Autodesk Fusion 360 part; units mm, degrees
(part 3 of 8)
sketch "SW2 receiver profile" plane through (0, -2.1431, 24.4961) normal (0, -0.087156, 0.996195) x (1, 0, 0)
  line L0 (30.8, 17.6972) -> (49.2, 17.6972)
  line L1 (49.2, 17.6972) -> (49.2, 35.2972)
  line L2 (49.2, 35.2972) -> (30.8, 35.2972)
  line L3 (30.8, 35.2972) -> (30.8, 17.6972)
  dimension "d1000" = 30.8
  dimension "d1001" = 17.6972
  dimension "d1002" = 18.4
  dimension "d1003" = 17.6
  constraint horizontal L0
  constraint vertical L1
  constraint horizontal L2
  constraint vertical L3
  measures "d1000" horizontal distance of origin L0.start
  measures "d1001" vertical distance of origin L0.start
  measures "d1002" distance of L0.start L0.end
  measures "d1003" distance of L0.end L1.end
extrude "SW2 integrated receiver" add sketch "SW2 receiver profile" against normal blind 11.5 bodies 2
sketch "SW2 switch lower clearance profile" plane through (0, -2.1431, 24.4961) normal (0, -0.087156, 0.996195) x (1, 0, 0)
  line L0 (32, 18.4972) -> (48, 18.4972)
  line L1 (48, 18.4972) -> (48, 34.4972)
  line L2 (48, 34.4972) -> (32, 34.4972)
  line L3 (32, 34.4972) -> (32, 18.4972)
  dimension "d1006" = 32
  dimension "d1007" = 18.4972
  dimension "d1008" = 16
  dimension "d1009" = 16
  constraint horizontal L0
  constraint vertical L1
  constraint horizontal L2
  constraint vertical L3
  measures "d1006" horizontal distance of origin L0.start
  measures "d1007" vertical distance of origin L0.start
  measures "d1008" distance of L0.start L0.end
  measures "d1009" distance of L0.end L1.end
extrude "SW2 switch lower clearance" cut sketch "SW2 switch lower clearance profile" against normal blind 5.5 bodies 2
sketch "SW2 holder pocket profile" plane through (0, -1.6638, 19.017) normal (0, -0.087156, 0.996195) x (1, 0, 0)
  line L0 (34.2843, 21.4226) -> (45.7157, 21.4226)
  line L1 (45.7157, 21.4226) -> (45.7157, 31.5717)
  line L2 (45.7157, 31.5717) -> (34.2843, 31.5717)
  line L3 (34.2843, 31.5717) -> (34.2843, 21.4226)
  dimension "d1012" = 34.2843
  dimension "d1013" = 21.4226
  dimension "d1014" = 11.4315
  dimension "d1015" = 10.1491
  constraint horizontal L0
  constraint vertical L1
  constraint horizontal L2
  constraint vertical L3
  measures "d1012" horizontal distance of origin L0.start
  measures "d1013" vertical distance of origin L0.start
  measures "d1014" distance of L0.start L0.end
  measures "d1015" distance of L0.end L1.end
extrude "SW2 open-bottom holder pocket" cut sketch "SW2 holder pocket profile" against normal blind 6.2 bodies 2
sketch "SW2 spring 1 release 1 profile" plane through (0, -2.056, 23.4999) normal (0, -0.087156, 0.996195) x (1, 0, 0)
  line L0 (30.7, 28.5972) -> (34.2843, 28.5972)
  line L1 (34.2843, 28.5972) -> (34.2843, 29.1972)
  line L2 (34.2843, 29.1972) -> (30.7, 29.1972)
  line L3 (30.7, 29.1972) -> (30.7, 28.5972)
  dimension "d1018" = 30.7
  dimension "d1019" = 28.5972
  dimension "d1020" = 3.5843
  dimension "d1021" = 0.6
  constraint horizontal L0
  constraint vertical L1
  constraint horizontal L2
  constraint vertical L3
  measures "d1018" horizontal distance of origin L0.start
  measures "d1019" vertical distance of origin L0.start
  measures "d1020" distance of L0.start L0.end
  measures "d1021" distance of L0.end L1.end
extrude "SW2 spring 1 release 1" cut sketch "SW2 spring 1 release 1 profile" against normal blind 10.7 bodies 2
sketch "SW2 spring 1 release 2 profile" plane through (0, -2.056, 23.4999) normal (0, -0.087156, 0.996195) x (1, 0, 0)
  line L0 (30.7, 31.1972) -> (34.2843, 31.1972)
  line L1 (34.2843, 31.1972) -> (34.2843, 31.7972)
  line L2 (34.2843, 31.7972) -> (30.7, 31.7972)
  line L3 (30.7, 31.7972) -> (30.7, 31.1972)
  dimension "d1024" = 30.7
  dimension "d1025" = 31.1972
  dimension "d1026" = 3.5843
  dimension "d1027" = 0.6
  constraint horizontal L0
  constraint vertical L1
  constraint horizontal L2
  constraint vertical L3
  measures "d1024" horizontal distance of origin L0.start
  measures "d1025" vertical distance of origin L0.start
  measures "d1026" distance of L0.start L0.end
  measures "d1027" distance of L0.end L1.end
extrude "SW2 spring 1 release 2" cut sketch "SW2 spring 1 release 2 profile" against normal blind 10.7 bodies 2
sketch "SW2 spring 1 inner clearance profile" plane through (0, -1.6638, 19.017) normal (0, -0.087156, 0.996195) x (1, 0, 0)
  line L0 (31.6, 29.1972) -> (34.2843, 29.1972)
  line L1 (34.2843, 29.1972) -> (34.2843, 31.1972)
  line L2 (34.2843, 31.1972) -> (31.6, 31.1972)
  line L3 (31.6, 31.1972) -> (31.6, 29.1972)
  dimension "d1030" = 31.6
  dimension "d1031" = 29.1972
  dimension "d1032" = 2.6843
  dimension "d1033" = 2
  constraint horizontal L0
  constraint vertical L1
  constraint horizontal L2
  constraint vertical L3
  measures "d1030" horizontal distance of origin L0.start
  measures "d1031" vertical distance of origin L0.start
  measures "d1032" distance of L0.start L0.end
  measures "d1033" distance of L0.end L1.end
extrude "SW2 spring 1 inner clearance" cut sketch "SW2 spring 1 inner clearance profile" against normal blind 6.2 bodies 2
sketch "SW2 spring 1 hook profile" plane through (0, -1.2106, 13.8368) normal (0, -0.087156, 0.996195) x (1, 0, 0)
  line L0 (30.8, 29.1972) -> (34.7843, 29.1972)
  line L1 (34.7843, 29.1972) -> (34.7843, 31.1972)
  line L2 (34.7843, 31.1972) -> (30.8, 31.1972)
  line L3 (30.8, 31.1972) -> (30.8, 29.1972)
  dimension "d1036" = 30.8
  dimension "d1037" = 29.1972
  dimension "d1038" = 3.9843
  dimension "d1039" = 2
  constraint horizontal L0
  constraint vertical L1
  constraint horizontal L2
  constraint vertical L3
  measures "d1036" horizontal distance of origin L0.start
  measures "d1037" vertical distance of origin L0.start
  measures "d1038" distance of L0.start L0.end
  measures "d1039" distance of L0.end L1.end
extrude "SW2 spring 1 retaining hook" add sketch "SW2 spring 1 hook profile" against normal blind 0.8 bodies 2
chamfer "SW2 spring 1 45 degree lead-in" distance 0.35 angle 45 1 edges at (34.7843, 28.9414, 15.6717) tangent chain off on bodies 2
sketch "SW2 spring 2 release 1 profile" plane through (0, -2.056, 23.4999) normal (0, -0.087156, 0.996195) x (1, 0, 0)
  line L0 (45.7157, 28.5972) -> (49.3, 28.5972)
  line L1 (49.3, 28.5972) -> (49.3, 29.1972)
  line L2 (49.3, 29.1972) -> (45.7157, 29.1972)
  line L3 (45.7157, 29.1972) -> (45.7157, 28.5972)
  dimension "d1043" = 45.7157
  dimension "d1044" = 28.5972
  dimension "d1045" = 3.5843
  dimension "d1046" = 0.6
  constraint horizontal L0
  constraint vertical L1
  constraint horizontal L2
  constraint vertical L3
  measures "d1043" horizontal distance of origin L0.start
  measures "d1044" vertical distance of origin L0.start
  measures "d1045" distance of L0.start L0.end
  measures "d1046" distance of L0.end L1.end
extrude "SW2 spring 2 release 1" cut sketch "SW2 spring 2 release 1 profile" against normal blind 10.7 bodies 2
sketch "SW2 spring 2 release 2 profile" plane through (0, -2.056, 23.4999) normal (0, -0.087156, 0.996195) x (1, 0, 0)
  line L0 (45.7157, 31.1972) -> (49.3, 31.1972)
  line L1 (49.3, 31.1972) -> (49.3, 31.7972)
  line L2 (49.3, 31.7972) -> (45.7157, 31.7972)
  line L3 (45.7157, 31.7972) -> (45.7157, 31.1972)
  dimension "d1049" = 45.7157
  dimension "d1050" = 31.1972
  dimension "d1051" = 3.5843
  dimension "d1052" = 0.6
  constraint horizontal L0
  constraint vertical L1
  constraint horizontal L2
  constraint vertical L3
  measures "d1049" horizontal distance of origin L0.start
  measures "d1050" vertical distance of origin L0.start
  measures "d1051" distance of L0.start L0.end
  measures "d1052" distance of L0.end L1.end
extrude "SW2 spring 2 release 2" cut sketch "SW2 spring 2 release 2 profile" against normal blind 10.7 bodies 2
sketch "SW2 spring 2 inner clearance profile" plane through (0, -1.6638, 19.017) normal (0, -0.087156, 0.996195) x (1, 0, 0)
  line L0 (45.7157, 29.1972) -> (48.4, 29.1972)
  line L1 (48.4, 29.1972) -> (48.4, 31.1972)
  line L2 (48.4, 31.1972) -> (45.7157, 31.1972)
  line L3 (45.7157, 31.1972) -> (45.7157, 29.1972)
  dimension "d1055" = 45.7157
  dimension "d1056" = 29.1972
  dimension "d1057" = 2.6843
  dimension "d1058" = 2
  constraint horizontal L0
  constraint vertical L1
  constraint horizontal L2
  constraint vertical L3
  measures "d1055" horizontal distance of origin L0.start
  measures "d1056" vertical distance of origin L0.start
  measures "d1057" distance of L0.start L0.end
  measures "d1058" distance of L0.end L1.end
extrude "SW2 spring 2 inner clearance" cut sketch "SW2 spring 2 inner clearance profile" against normal blind 6.2 bodies 2
sketch "SW2 spring 2 hook profile" plane through (0, -1.2106, 13.8368) normal (0, -0.087156, 0.996195) x (1, 0, 0)
  line L0 (45.2157, 29.1972) -> (49.2, 29.1972)
  line L1 (49.2, 29.1972) -> (49.2, 31.1972)
  line L2 (49.2, 31.1972) -> (45.2157, 31.1972)
  line L3 (45.2157, 31.1972) -> (45.2157, 29.1972)
  dimension "d1061" = 45.2157
  dimension "d1062" = 29.1972
  dimension "d1063" = 3.9843
  dimension "d1064" = 2
  constraint horizontal L0
  constraint vertical L1
  constraint horizontal L2
  constraint vertical L3
  measures "d1061" horizontal distance of origin L0.start
  measures "d1062" vertical distance of origin L0.start
  measures "d1063" distance of L0.start L0.end
  measures "d1064" distance of L0.end L1.end
extrude "SW2 spring 2 retaining hook" add sketch "SW2 spring 2 hook profile" against normal blind 0.8 bodies 2
chamfer "SW2 spring 2 45 degree lead-in" distance 0.35 angle 45 1 edges at (45.2157, 28.9414, 15.6717) tangent chain off on bodies 2
sketch "SW2 support 1 reinforced stem profile" plane through (0, 0, 2) normal (0, 0, 1) x (1, 0, 0)
  line L0 (36.3, 21.5078) -> (38.7, 21.5078)
  line L1 (38.7, 21.5078) -> (38.7, 26.5078)
  line L2 (38.7, 26.5078) -> (36.3, 26.5078)
  line L3 (36.3, 26.5078) -> (36.3, 21.5078)
  dimension "d1068" = 36.3
  dimension "d1069" = 21.5078
  dimension "d1070" = 2.4
  dimension "d1071" = 5
  constraint horizontal L0
  constraint vertical L1
  constraint horizontal L2
  constraint vertical L3
  measures "d1068" horizontal distance of origin L0.start
  measures "d1069" vertical distance of origin L0.start
  measures "d1070" distance of L0.start L0.end
  measures "d1071" distance of L0.end L1.end
extrude "SW2 support 1 reinforced stem" add sketch "SW2 support 1 reinforced stem profile" along normal blind 11.8423 bodies 3
sketch "SW2 support 1 profile" plane through (0, 0, 2) normal (0, 0, 1) x (1, 0, 0)
  line L0 (37, 22.5078) -> (38, 22.5078)
  line L1 (38, 22.5078) -> (38, 25.5078)
  line L2 (38, 25.5078) -> (37, 25.5078)
  line L3 (37, 25.5078) -> (37, 22.5078)
  dimension "d1074" = 37
  dimension "d1075" = 22.5078
  dimension "d1076" = 1
  dimension "d1077" = 3
  constraint horizontal L0
  constraint vertical L1
  constraint horizontal L2
  constraint vertical L3
  measures "d1074" horizontal distance of origin L0.start
  measures "d1075" vertical distance of origin L0.start
  measures "d1076" distance of L0.start L0.end
  measures "d1077" distance of L0.end L1.end
extrude "SW2 support 1" add sketch "SW2 support 1 profile" along normal blind 14.3423 bodies 3
sketch "SW2 support 1 cap profile" plane through (0, -1.1931, 13.6376) normal (0, -0.087156, 0.996195) x (1, 0, 0)
  line L0 (36.9, 23.2972) -> (38.1, 23.2972)
  line L1 (38.1, 23.2972) -> (38.1, 27.2972)
  line L2 (38.1, 27.2972) -> (36.9, 27.2972)
  line L3 (36.9, 27.2972) -> (36.9, 23.2972)
  dimension "d1080" = 36.9
  dimension "d1081" = 23.2972
  dimension "d1082" = 1.2
  dimension "d1083" = 4
  constraint horizontal L0
  constraint vertical L1
  constraint horizontal L2
  constraint vertical L3
  measures "d1080" horizontal distance of origin L0.start
  measures "d1081" vertical distance of origin L0.start
  measures "d1082" distance of L0.start L0.end
  measures "d1083" distance of L0.end L1.end
extrude "SW2 support 1 inclined cap" cut sketch "SW2 support 1 cap profile" along normal blind 39.0612 bodies 3
sketch "SW2 support 2 reinforced stem profile" plane through (0, 0, 2) normal (0, 0, 1) x (1, 0, 0)
  line L0 (41.3, 21.5078) -> (43.7, 21.5078)
  line L1 (43.7, 21.5078) -> (43.7, 26.5078)
  line L2 (43.7, 26.5078) -> (41.3, 26.5078)
  line L3 (41.3, 26.5078) -> (41.3, 21.5078)
  dimension "d1086" = 41.3
  dimension "d1087" = 21.5078
  dimension "d1088" = 2.4
  dimension "d1089" = 5
  constraint horizontal L0
  constraint vertical L1
  constraint horizontal L2
  constraint vertical L3
  measures "d1086" horizontal distance of origin L0.start
  measures "d1087" vertical distance of origin L0.start
  measures "d1088" distance of L0.start L0.end
  measures "d1089" distance of L0.end L1.end
extrude "SW2 support 2 reinforced stem" add sketch "SW2 support 2 reinforced stem profile" along normal blind 11.8423 bodies 3
sketch "SW2 support 2 profile" plane through (0, 0, 2) normal (0, 0, 1) x (1, 0, 0)
  line L0 (42, 22.5078) -> (43, 22.5078)
  line L1 (43, 22.5078) -> (43, 25.5078)
  line L2 (43, 25.5078) -> (42, 25.5078)
  line L3 (42, 25.5078) -> (42, 22.5078)
  dimension "d1092" = 42
  dimension "d1093" = 22.5078
  dimension "d1094" = 1
  dimension "d1095" = 3
  constraint horizontal L0
  constraint vertical L1
  constraint horizontal L2
  constraint vertical L3
  measures "d1092" horizontal distance of origin L0.start
  measures "d1093" vertical distance of origin L0.start
  measures "d1094" distance of L0.start L0.end
  measures "d1095" distance of L0.end L1.end
extrude "SW2 support 2" add sketch "SW2 support 2 profile" along normal blind 14.3423 bodies 3
sketch "SW2 support 2 cap profile" plane through (0, -1.1931, 13.6376) normal (0, -0.087156, 0.996195) x (1, 0, 0)
  line L0 (41.9, 23.2972) -> (43.1, 23.2972)
  line L1 (43.1, 23.2972) -> (43.1, 27.2972)
  line L2 (43.1, 27.2972) -> (41.9, 27.2972)
  line L3 (41.9, 27.2972) -> (41.9, 23.2972)
  dimension "d1098" = 41.9
  dimension "d1099" = 23.2972
  dimension "d1100" = 1.2
  dimension "d1101" = 4
  constraint horizontal L0
  constraint vertical L1
  constraint horizontal L2
  constraint vertical L3
  measures "d1098" horizontal distance of origin L0.start
  measures "d1099" vertical distance of origin L0.start
  measures "d1100" distance of L0.start L0.end
  measures "d1101" distance of L0.end L1.end
extrude "SW2 support 2 inclined cap" cut sketch "SW2 support 2 cap profile" along normal blind 39.0612 bodies 3
sketch "SW3 receiver profile" plane through (0, -2.1431, 24.4961) normal (0, -0.087156, 0.996195) x (1, 0, 0)
  line L0 (55.3, 17.6972) -> (73.7, 17.6972)
  line L1 (73.7, 17.6972) -> (73.7, 35.2972)
  line L2 (73.7, 35.2972) -> (55.3, 35.2972)
  line L3 (55.3, 35.2972) -> (55.3, 17.6972)
  dimension "d1104" = 55.3
  dimension "d1105" = 17.6972
  dimension "d1106" = 18.4
  dimension "d1107" = 17.6
  constraint horizontal L0
  constraint vertical L1
  constraint horizontal L2
  constraint vertical L3
  measures "d1104" horizontal distance of origin L0.start
  measures "d1105" vertical distance of origin L0.start
  measures "d1106" distance of L0.start L0.end
  measures "d1107" distance of L0.end L1.end
extrude "SW3 integrated receiver" add sketch "SW3 receiver profile" against normal blind 11.5 bodies 2
sketch "SW3 switch lower clearance profile" plane through (0, -2.1431, 24.4961) normal (0, -0.087156, 0.996195) x (1, 0, 0)
  line L0 (56.5, 18.4972) -> (72.5, 18.4972)
  line L1 (72.5, 18.4972) -> (72.5, 34.4972)
  line L2 (72.5, 34.4972) -> (56.5, 34.4972)
  line L3 (56.5, 34.4972) -> (56.5, 18.4972)
  dimension "d1110" = 56.5
  dimension "d1111" = 18.4972
  dimension "d1112" = 16
  dimension "d1113" = 16
  constraint horizontal L0
  constraint vertical L1
  constraint horizontal L2
  constraint vertical L3
  measures "d1110" horizontal distance of origin L0.start
  measures "d1111" vertical distance of origin L0.start
  measures "d1112" distance of L0.start L0.end
  measures "d1113" distance of L0.end L1.end
extrude "SW3 switch lower clearance" cut sketch "SW3 switch lower clearance profile" against normal blind 5.5 bodies 2
sketch "SW3 holder pocket profile" plane through (0, -1.6638, 19.017) normal (0, -0.087156, 0.996195) x (1, 0, 0)
  line L0 (58.7843, 21.4226) -> (70.2157, 21.4226)
  line L1 (70.2157, 21.4226) -> (70.2157, 31.5717)
  line L2 (70.2157, 31.5717) -> (58.7843, 31.5717)
  line L3 (58.7843, 31.5717) -> (58.7843, 21.4226)
  dimension "d1116" = 58.7843
  dimension "d1117" = 21.4226
  dimension "d1118" = 11.4315
  dimension "d1119" = 10.1491
  constraint horizontal L0
  constraint vertical L1
  constraint horizontal L2
  constraint vertical L3
  measures "d1116" horizontal distance of origin L0.start
  measures "d1117" vertical distance of origin L0.start
  measures "d1118" distance of L0.start L0.end
  measures "d1119" distance of L0.end L1.end
extrude "SW3 open-bottom holder pocket" cut sketch "SW3 holder pocket profile" against normal blind 6.2 bodies 2
sketch "SW3 spring 1 release 1 profile" plane through (0, -2.056, 23.4999) normal (0, -0.087156, 0.996195) x (1, 0, 0)
  line L0 (55.2, 28.5972) -> (58.7843, 28.5972)
  line L1 (58.7843, 28.5972) -> (58.7843, 29.1972)
  line L2 (58.7843, 29.1972) -> (55.2, 29.1972)
  line L3 (55.2, 29.1972) -> (55.2, 28.5972)
  dimension "d1122" = 55.2
  dimension "d1123" = 28.5972
  dimension "d1124" = 3.5843
  dimension "d1125" = 0.6
  constraint horizontal L0
  constraint vertical L1
  constraint horizontal L2
  constraint vertical L3
  measures "d1122" horizontal distance of origin L0.start
  measures "d1123" vertical distance of origin L0.start
  measures "d1124" distance of L0.start L0.end
  measures "d1125" distance of L0.end L1.end
extrude "SW3 spring 1 release 1" cut sketch "SW3 spring 1 release 1 profile" against normal blind 10.7 bodies 2
sketch "SW3 spring 1 release 2 profile" plane through (0, -2.056, 23.4999) normal (0, -0.087156, 0.996195) x (1, 0, 0)
  line L0 (55.2, 31.1972) -> (58.7843, 31.1972)
  line L1 (58.7843, 31.1972) -> (58.7843, 31.7972)
  line L2 (58.7843, 31.7972) -> (55.2, 31.7972)
  line L3 (55.2, 31.7972) -> (55.2, 31.1972)
  dimension "d1128" = 55.2
  dimension "d1129" = 31.1972
  dimension "d1130" = 3.5843
  dimension "d1131" = 0.6
  constraint horizontal L0
  constraint vertical L1
  constraint horizontal L2
  constraint vertical L3
  measures "d1128" horizontal distance of origin L0.start
  measures "d1129" vertical distance of origin L0.start
  measures "d1130" distance of L0.start L0.end
  measures "d1131" distance of L0.end L1.end
extrude "SW3 spring 1 release 2" cut sketch "SW3 spring 1 release 2 profile" against normal blind 10.7 bodies 2
sketch "SW3 spring 1 inner clearance profile" plane through (0, -1.6638, 19.017) normal (0, -0.087156, 0.996195) x (1, 0, 0)
  line L0 (56.1, 29.1972) -> (58.7843, 29.1972)
  line L1 (58.7843, 29.1972) -> (58.7843, 31.1972)
  line L2 (58.7843, 31.1972) -> (56.1, 31.1972)
  line L3 (56.1, 31.1972) -> (56.1, 29.1972)
  dimension "d1134" = 56.1
  dimension "d1135" = 29.1972
  dimension "d1136" = 2.6843
  dimension "d1137" = 2
  constraint horizontal L0
  constraint vertical L1
  constraint horizontal L2
  constraint vertical L3
  measures "d1134" horizontal distance of origin L0.start
  measures "d1135" vertical distance of origin L0.start
  measures "d1136" distance of L0.start L0.end
  measures "d1137" distance of L0.end L1.end
extrude "SW3 spring 1 inner clearance" cut sketch "SW3 spring 1 inner clearance profile" against normal blind 6.2 bodies 2
sketch "SW3 spring 1 hook profile" plane through (0, -1.2106, 13.8368) normal (0, -0.087156, 0.996195) x (1, 0, 0)
  line L0 (55.3, 29.1972) -> (59.2843, 29.1972)
  line L1 (59.2843, 29.1972) -> (59.2843, 31.1972)
  line L2 (59.2843, 31.1972) -> (55.3, 31.1972)
  line L3 (55.3, 31.1972) -> (55.3, 29.1972)
  dimension "d1140" = 55.3
  dimension "d1141" = 29.1972
  dimension "d1142" = 3.9843
  dimension "d1143" = 2
  constraint horizontal L0
  constraint vertical L1
  constraint horizontal L2
  constraint vertical L3
  measures "d1140" horizontal distance of origin L0.start
  measures "d1141" vertical distance of origin L0.start
  measures "d1142" distance of L0.start L0.end
  measures "d1143" distance of L0.end L1.end
extrude "SW3 spring 1 retaining hook" add sketch "SW3 spring 1 hook profile" against normal blind 0.8 bodies 2
chamfer "SW3 spring 1 45 degree lead-in" distance 0.35 angle 45 1 edges at (59.2843, 28.9414, 15.6717) tangent chain off on bodies 2
sketch "SW3 spring 2 release 1 profile" plane through (0, -2.056, 23.4999) normal (0, -0.087156, 0.996195) x (1, 0, 0)
  line L0 (70.2157, 28.5972) -> (73.8, 28.5972)
  line L1 (73.8, 28.5972) -> (73.8, 29.1972)
  line L2 (73.8, 29.1972) -> (70.2157, 29.1972)
  line L3 (70.2157, 29.1972) -> (70.2157, 28.5972)
  dimension "d1147" = 70.2157
  dimension "d1148" = 28.5972
  dimension "d1149" = 3.5843
  dimension "d1150" = 0.6
  constraint horizontal L0
  constraint vertical L1
  constraint horizontal L2
  constraint vertical L3
  measures "d1147" horizontal distance of origin L0.start
  measures "d1148" vertical distance of origin L0.start
  measures "d1149" distance of L0.start L0.end
  measures "d1150" distance of L0.end L1.end
extrude "SW3 spring 2 release 1" cut sketch "SW3 spring 2 release 1 profile" against normal blind 10.7 bodies 2
sketch "SW3 spring 2 release 2 profile" plane through (0, -2.056, 23.4999) normal (0, -0.087156, 0.996195) x (1, 0, 0)
  line L0 (70.2157, 31.1972) -> (73.8, 31.1972)
  line L1 (73.8, 31.1972) -> (73.8, 31.7972)
  line L2 (73.8, 31.7972) -> (70.2157, 31.7972)
  line L3 (70.2157, 31.7972) -> (70.2157, 31.1972)
  dimension "d1153" = 70.2157
  dimension "d1154" = 31.1972
  dimension "d1155" = 3.5843
  dimension "d1156" = 0.6
  constraint horizontal L0
  constraint vertical L1
  constraint horizontal L2
  constraint vertical L3
  measures "d1153" horizontal distance of origin L0.start
  measures "d1154" vertical distance of origin L0.start
  measures "d1155" distance of L0.start L0.end
  measures "d1156" distance of L0.end L1.end
extrude "SW3 spring 2 release 2" cut sketch "SW3 spring 2 release 2 profile" against normal blind 10.7 bodies 2
sketch "SW3 spring 2 inner clearance profile" plane through (0, -1.6638, 19.017) normal (0, -0.087156, 0.996195) x (1, 0, 0)
  line L0 (70.2157, 29.1972) -> (72.9, 29.1972)
  line L1 (72.9, 29.1972) -> (72.9, 31.1972)
  line L2 (72.9, 31.1972) -> (70.2157, 31.1972)
  line L3 (70.2157, 31.1972) -> (70.2157, 29.1972)
  dimension "d1159" = 70.2157
  dimension "d1160" = 29.1972
  dimension "d1161" = 2.6843
  dimension "d1162" = 2
  constraint horizontal L0
  constraint vertical L1
  constraint horizontal L2
  constraint vertical L3
  measures "d1159" horizontal distance of origin L0.start
  measures "d1160" vertical distance of origin L0.start
  measures "d1161" distance of L0.start L0.end
  measures "d1162" distance of L0.end L1.end
extrude "SW3 spring 2 inner clearance" cut sketch "SW3 spring 2 inner clearance profile" against normal blind 6.2 bodies 2
sketch "SW3 spring 2 hook profile" plane through (0, -1.2106, 13.8368) normal (0, -0.087156, 0.996195) x (1, 0, 0)
  line L0 (69.7157, 29.1972) -> (73.7, 29.1972)
  line L1 (73.7, 29.1972) -> (73.7, 31.1972)
  line L2 (73.7, 31.1972) -> (69.7157, 31.1972)
  line L3 (69.7157, 31.1972) -> (69.7157, 29.1972)
  dimension "d1165" = 69.7157
  dimension "d1166" = 29.1972
  dimension "d1167" = 3.9843
  dimension "d1168" = 2
  constraint horizontal L0
  constraint vertical L1
  constraint horizontal L2
  constraint vertical L3
  measures "d1165" horizontal distance of origin L0.start
  measures "d1166" vertical distance of origin L0.start
  measures "d1167" distance of L0.start L0.end
  measures "d1168" distance of L0.end L1.end
extrude "SW3 spring 2 retaining hook" add sketch "SW3 spring 2 hook profile" against normal blind 0.8 bodies 2
chamfer "SW3 spring 2 45 degree lead-in" distance 0.35 angle 45 1 edges at (69.7157, 28.9414, 15.6717) tangent chain off on bodies 2
sketch "SW3 support 1 reinforced stem profile" plane through (0, 0, 2) normal (0, 0, 1) x (1, 0, 0)
  line L0 (60.8, 21.5078) -> (63.2, 21.5078)
  line L1 (63.2, 21.5078) -> (63.2, 26.5078)
  line L2 (63.2, 26.5078) -> (60.8, 26.5078)
  line L3 (60.8, 26.5078) -> (60.8, 21.5078)
  dimension "d1172" = 60.8
  dimension "d1173" = 21.5078
  dimension "d1174" = 2.4
  dimension "d1175" = 5
  constraint horizontal L0
  constraint vertical L1
  constraint horizontal L2
  constraint vertical L3
  measures "d1172" horizontal distance of origin L0.start
  measures "d1173" vertical distance of origin L0.start
  measures "d1174" distance of L0.start L0.end
  measures "d1175" distance of L0.end L1.end
extrude "SW3 support 1 reinforced stem" add sketch "SW3 support 1 reinforced stem profile" along normal blind 11.8423 bodies 3
sketch "SW3 support 1 profile" plane through (0, 0, 2) normal (0, 0, 1) x (1, 0, 0)
  line L0 (61.5, 22.5078) -> (62.5, 22.5078)
  line L1 (62.5, 22.5078) -> (62.5, 25.5078)
  line L2 (62.5, 25.5078) -> (61.5, 25.5078)
  line L3 (61.5, 25.5078) -> (61.5, 22.5078)
  dimension "d1178" = 61.5
  dimension "d1179" = 22.5078
  dimension "d1180" = 1
  dimension "d1181" = 3
  constraint horizontal L0
  constraint vertical L1
  constraint horizontal L2
  constraint vertical L3
  measures "d1178" horizontal distance of origin L0.start
  measures "d1179" vertical distance of origin L0.start
  measures "d1180" distance of L0.start L0.end
  measures "d1181" distance of L0.end L1.end
extrude "SW3 support 1" add sketch "SW3 support 1 profile" along normal blind 14.3423 bodies 3
sketch "SW3 support 1 cap profile" plane through (0, -1.1931, 13.6376) normal (0, -0.087156, 0.996195) x (1, 0, 0)
  line L0 (61.4, 23.2972) -> (62.6, 23.2972)
  line L1 (62.6, 23.2972) -> (62.6, 27.2972)
  line L2 (62.6, 27.2972) -> (61.4, 27.2972)
  line L3 (61.4, 27.2972) -> (61.4, 23.2972)
  dimension "d1184" = 61.4
  dimension "d1185" = 23.2972
  dimension "d1186" = 1.2
  dimension "d1187" = 4
  constraint horizontal L0
  constraint vertical L1
  constraint horizontal L2
  constraint vertical L3
  measures "d1184" horizontal distance of origin L0.start
  measures "d1185" vertical distance of origin L0.start
  measures "d1186" distance of L0.start L0.end
  measures "d1187" distance of L0.end L1.end
extrude "SW3 support 1 inclined cap" cut sketch "SW3 support 1 cap profile" along normal blind 39.0612 bodies 3
sketch "SW3 support 2 reinforced stem profile" plane through (0, 0, 2) normal (0, 0, 1) x (1, 0, 0)
  line L0 (65.8, 21.5078) -> (68.2, 21.5078)
  line L1 (68.2, 21.5078) -> (68.2, 26.5078)
  line L2 (68.2, 26.5078) -> (65.8, 26.5078)
  line L3 (65.8, 26.5078) -> (65.8, 21.5078)
  dimension "d1190" = 65.8
  dimension "d1191" = 21.5078
  dimension "d1192" = 2.4
  dimension "d1193" = 5
  constraint horizontal L0
  constraint vertical L1
  constraint horizontal L2
  constraint vertical L3
  measures "d1190" horizontal distance of origin L0.start
  measures "d1191" vertical distance of origin L0.start
  measures "d1192" distance of L0.start L0.end
  measures "d1193" distance of L0.end L1.end
extrude "SW3 support 2 reinforced stem" add sketch "SW3 support 2 reinforced stem profile" along normal blind 11.8423 bodies 3
sketch "SW3 support 2 profile" plane through (0, 0, 2) normal (0, 0, 1) x (1, 0, 0)
  line L0 (66.5, 22.5078) -> (67.5, 22.5078)
  line L1 (67.5, 22.5078) -> (67.5, 25.5078)
  line L2 (67.5, 25.5078) -> (66.5, 25.5078)
  line L3 (66.5, 25.5078) -> (66.5, 22.5078)
  dimension "d1196" = 66.5
  dimension "d1197" = 22.5078
  dimension "d1198" = 1
  dimension "d1199" = 3
  constraint horizontal L0
  constraint vertical L1
  constraint horizontal L2
  constraint vertical L3
  measures "d1196" horizontal distance of origin L0.start
  measures "d1197" vertical distance of origin L0.start
  measures "d1198" distance of L0.start L0.end
  measures "d1199" distance of L0.end L1.end
extrude "SW3 support 2" add sketch "SW3 support 2 profile" along normal blind 14.3423 bodies 3
sketch "SW3 support 2 cap profile" plane through (0, -1.1931, 13.6376) normal (0, -0.087156, 0.996195) x (1, 0, 0)
  line L0 (66.4, 23.2972) -> (67.6, 23.2972)
  line L1 (67.6, 23.2972) -> (67.6, 27.2972)
  line L2 (67.6, 27.2972) -> (66.4, 27.2972)
  line L3 (66.4, 27.2972) -> (66.4, 23.2972)
  dimension "d1202" = 66.4
  dimension "d1203" = 23.2972
  dimension "d1204" = 1.2
  dimension "d1205" = 4
  constraint horizontal L0
  constraint vertical L1
  constraint horizontal L2
  constraint vertical L3
  measures "d1202" horizontal distance of origin L0.start
  measures "d1203" vertical distance of origin L0.start
  measures "d1204" distance of L0.start L0.end
  measures "d1205" distance of L0.end L1.end
extrude "SW3 support 2 inclined cap" cut sketch "SW3 support 2 cap profile" along normal blind 39.0612 bodies 3
sketch "SW4 receiver profile" plane through (0, -2.1431, 24.4961) normal (0, -0.087156, 0.996195) x (1, 0, 0)
  line L0 (6.3, 42.1972) -> (24.7, 42.1972)
  line L1 (24.7, 42.1972) -> (24.7, 59.7972)
  line L2 (24.7, 59.7972) -> (6.3, 59.7972)
  line L3 (6.3, 59.7972) -> (6.3, 42.1972)
  dimension "d1208" = 6.3
  dimension "d1209" = 42.1972
  dimension "d1210" = 18.4
  dimension "d1211" = 17.6
  constraint horizontal L0
  constraint vertical L1
  constraint horizontal L2
  constraint vertical L3
  measures "d1208" horizontal distance of origin L0.start
  measures "d1209" vertical distance of origin L0.start
  measures "d1210" distance of L0.start L0.end
  measures "d1211" distance of L0.end L1.end
extrude "SW4 integrated receiver" add sketch "SW4 receiver profile" against normal blind 11.5 bodies 2
sketch "SW4 switch lower clearance profile" plane through (0, -2.1431, 24.4961) normal (0, -0.087156, 0.996195) x (1, 0, 0)
  line L0 (7.5, 42.9972) -> (23.5, 42.9972)
  line L1 (23.5, 42.9972) -> (23.5, 58.9972)
  line L2 (23.5, 58.9972) -> (7.5, 58.9972)
  line L3 (7.5, 58.9972) -> (7.5, 42.9972)
  dimension "d1214" = 7.5
  dimension "d1215" = 42.9972
  dimension "d1216" = 16
  dimension "d1217" = 16
  constraint horizontal L0
  constraint vertical L1
  constraint horizontal L2
  constraint vertical L3
  measures "d1214" horizontal distance of origin L0.start
  measures "d1215" vertical distance of origin L0.start
  measures "d1216" distance of L0.start L0.end
  measures "d1217" distance of L0.end L1.end
extrude "SW4 switch lower clearance" cut sketch "SW4 switch lower clearance profile" against normal blind 5.5 bodies 2
sketch "SW4 holder pocket profile" plane through (0, -1.6638, 19.017) normal (0, -0.087156, 0.996195) x (1, 0, 0)
  line L0 (9.7843, 45.9226) -> (21.2157, 45.9226)
  line L1 (21.2157, 45.9226) -> (21.2157, 56.0717)
  line L2 (21.2157, 56.0717) -> (9.7843, 56.0717)
  line L3 (9.7843, 56.0717) -> (9.7843, 45.9226)
  dimension "d1220" = 9.7843
  dimension "d1221" = 45.9226
  dimension "d1222" = 11.4315
  dimension "d1223" = 10.1491
  constraint horizontal L0
  constraint vertical L1
  constraint horizontal L2
  constraint vertical L3
  measures "d1220" horizontal distance of origin L0.start
  measures "d1221" vertical distance of origin L0.start
  measures "d1222" distance of L0.start L0.end
  measures "d1223" distance of L0.end L1.end
extrude "SW4 open-bottom holder pocket" cut sketch "SW4 holder pocket profile" against normal blind 6.2 bodies 2
sketch "SW4 spring 1 release 1 profile" plane through (0, -2.056, 23.4999) normal (0, -0.087156, 0.996195) x (1, 0, 0)
  line L0 (6.2, 53.0972) -> (9.7843, 53.0972)
  line L1 (9.7843, 53.0972) -> (9.7843, 53.6972)
  line L2 (9.7843, 53.6972) -> (6.2, 53.6972)
  line L3 (6.2, 53.6972) -> (6.2, 53.0972)
  dimension "d1226" = 6.2
  dimension "d1227" = 53.0972
  dimension "d1228" = 3.5843
  dimension "d1229" = 0.6
  constraint horizontal L0
  constraint vertical L1
  constraint horizontal L2
  constraint vertical L3
  measures "d1226" horizontal distance of origin L0.start
  measures "d1227" vertical distance of origin L0.start
  measures "d1228" distance of L0.start L0.end
  measures "d1229" distance of L0.end L1.end
extrude "SW4 spring 1 release 1" cut sketch "SW4 spring 1 release 1 profile" against normal blind 10.7 bodies 2
sketch "SW4 spring 1 release 2 profile" plane through (0, -2.056, 23.4999) normal (0, -0.087156, 0.996195) x (1, 0, 0)
  line L0 (6.2, 55.6972) -> (9.7843, 55.6972)
  line L1 (9.7843, 55.6972) -> (9.7843, 56.2972)
  line L2 (9.7843, 56.2972) -> (6.2, 56.2972)
  line L3 (6.2, 56.2972) -> (6.2, 55.6972)
  dimension "d1232" = 6.2
  dimension "d1233" = 55.6972
  dimension "d1234" = 3.5843
  dimension "d1235" = 0.6
  constraint horizontal L0
  constraint vertical L1
  constraint horizontal L2
  constraint vertical L3
  measures "d1232" horizontal distance of origin L0.start
  measures "d1233" vertical distance of origin L0.start
  measures "d1234" distance of L0.start L0.end
  measures "d1235" distance of L0.end L1.end
extrude "SW4 spring 1 release 2" cut sketch "SW4 spring 1 release 2 profile" against normal blind 10.7 bodies 2
sketch "SW4 spring 1 inner clearance profile" plane through (0, -1.6638, 19.017) normal (0, -0.087156, 0.996195) x (1, 0, 0)
  line L0 (7.1, 53.6972) -> (9.7843, 53.6972)
  line L1 (9.7843, 53.6972) -> (9.7843, 55.6972)
  line L2 (9.7843, 55.6972) -> (7.1, 55.6972)
  line L3 (7.1, 55.6972) -> (7.1, 53.6972)
  dimension "d1238" = 7.1
  dimension "d1239" = 53.6972
  dimension "d1240" = 2.6843
  dimension "d1241" = 2
  constraint horizontal L0
  constraint vertical L1
  constraint horizontal L2
  constraint vertical L3
  measures "d1238" horizontal distance of origin L0.start
  measures "d1239" vertical distance of origin L0.start
  measures "d1240" distance of L0.start L0.end
  measures "d1241" distance of L0.end L1.end
extrude "SW4 spring 1 inner clearance" cut sketch "SW4 spring 1 inner clearance profile" against normal blind 6.2 bodies 2
sketch "SW4 spring 1 hook profile" plane through (0, -1.2106, 13.8368) normal (0, -0.087156, 0.996195) x (1, 0, 0)
  line L0 (6.3, 53.6972) -> (10.2843, 53.6972)
  line L1 (10.2843, 53.6972) -> (10.2843, 55.6972)
  line L2 (10.2843, 55.6972) -> (6.3, 55.6972)
  line L3 (6.3, 55.6972) -> (6.3, 53.6972)
  dimension "d1244" = 6.3
  dimension "d1245" = 53.6972
  dimension "d1246" = 3.9843
  dimension "d1247" = 2
  constraint horizontal L0
  constraint vertical L1
  constraint horizontal L2
  constraint vertical L3
  measures "d1244" horizontal distance of origin L0.start
  measures "d1245" vertical distance of origin L0.start
  measures "d1246" distance of L0.start L0.end
  measures "d1247" distance of L0.end L1.end
extrude "SW4 spring 1 retaining hook" add sketch "SW4 spring 1 hook profile" against normal blind 0.8 bodies 2
chamfer "SW4 spring 1 45 degree lead-in" distance 0.35 angle 45 1 edges at (10.2843, 53.3482, 17.807) tangent chain off on bodies 2
sketch "SW4 spring 2 release 1 profile" plane through (0, -2.056, 23.4999) normal (0, -0.087156, 0.996195) x (1, 0, 0)
  line L0 (21.2157, 53.0972) -> (24.8, 53.0972)
  line L1 (24.8, 53.0972) -> (24.8, 53.6972)
  line L2 (24.8, 53.6972) -> (21.2157, 53.6972)
  line L3 (21.2157, 53.6972) -> (21.2157, 53.0972)
  dimension "d1251" = 21.2157
  dimension "d1252" = 53.0972
  dimension "d1253" = 3.5843
  dimension "d1254" = 0.6
  constraint horizontal L0
  constraint vertical L1
  constraint horizontal L2
  constraint vertical L3
  measures "d1251" horizontal distance of origin L0.start
  measures "d1252" vertical distance of origin L0.start
  measures "d1253" distance of L0.start L0.end
  measures "d1254" distance of L0.end L1.end
extrude "SW4 spring 2 release 1" cut sketch "SW4 spring 2 release 1 profile" against normal blind 10.7 bodies 2
sketch "SW4 spring 2 release 2 profile" plane through (0, -2.056, 23.4999) normal (0, -0.087156, 0.996195) x (1, 0, 0)
  line L0 (21.2157, 55.6972) -> (24.8, 55.6972)
  line L1 (24.8, 55.6972) -> (24.8, 56.2972)
  line L2 (24.8, 56.2972) -> (21.2157, 56.2972)
  line L3 (21.2157, 56.2972) -> (21.2157, 55.6972)
  dimension "d1257" = 21.2157
  dimension "d1258" = 55.6972
  dimension "d1259" = 3.5843
  dimension "d1260" = 0.6
  constraint horizontal L0
  constraint vertical L1
  constraint horizontal L2
  constraint vertical L3
  measures "d1257" horizontal distance of origin L0.start
  measures "d1258" vertical distance of origin L0.start
  measures "d1259" distance of L0.start L0.end
  measures "d1260" distance of L0.end L1.end
extrude "SW4 spring 2 release 2" cut sketch "SW4 spring 2 release 2 profile" against normal blind 10.7 bodies 2
sketch "SW4 spring 2 inner clearance profile" plane through (0, -1.6638, 19.017) normal (0, -0.087156, 0.996195) x (1, 0, 0)
  line L0 (21.2157, 53.6972) -> (23.9, 53.6972)
  line L1 (23.9, 53.6972) -> (23.9, 55.6972)
  line L2 (23.9, 55.6972) -> (21.2157, 55.6972)
  line L3 (21.2157, 55.6972) -> (21.2157, 53.6972)
  dimension "d1263" = 21.2157
  dimension "d1264" = 53.6972
  dimension "d1265" = 2.6843
  dimension "d1266" = 2
  constraint horizontal L0
  constraint vertical L1
  constraint horizontal L2
  constraint vertical L3
  measures "d1263" horizontal distance of origin L0.start
  measures "d1264" vertical distance of origin L0.start
  measures "d1265" distance of L0.start L0.end
  measures "d1266" distance of L0.end L1.end
extrude "SW4 spring 2 inner clearance" cut sketch "SW4 spring 2 inner clearance profile" against normal blind 6.2 bodies 2
sketch "SW4 spring 2 hook profile" plane through (0, -1.2106, 13.8368) normal (0, -0.087156, 0.996195) x (1, 0, 0)
  line L0 (20.7157, 53.6972) -> (24.7, 53.6972)
  line L1 (24.7, 53.6972) -> (24.7, 55.6972)
  line L2 (24.7, 55.6972) -> (20.7157, 55.6972)
  line L3 (20.7157, 55.6972) -> (20.7157, 53.6972)
  dimension "d1269" = 20.7157
  dimension "d1270" = 53.6972
  dimension "d1271" = 3.9843
  dimension "d1272" = 2
  constraint horizontal L0
  constraint vertical L1
  constraint horizontal L2
  constraint vertical L3
  measures "d1269" horizontal distance of origin L0.start
  measures "d1270" vertical distance of origin L0.start
  measures "d1271" distance of L0.start L0.end
  measures "d1272" distance of L0.end L1.end
extrude "SW4 spring 2 retaining hook" add sketch "SW4 spring 2 hook profile" against normal blind 0.8 bodies 2
chamfer "SW4 spring 2 45 degree lead-in" distance 0.35 angle 45 1 edges at (20.7157, 53.3482, 17.807) tangent chain off on bodies 2
sketch "SW4 support 1 reinforced stem profile" plane through (0, 0, 2) normal (0, 0, 1) x (1, 0, 0)
  line L0 (11.8, 45.9145) -> (14.2, 45.9145)
  line L1 (14.2, 45.9145) -> (14.2, 50.9145)
  line L2 (14.2, 50.9145) -> (11.8, 50.9145)
  line L3 (11.8, 50.9145) -> (11.8, 45.9145)
  dimension "d1276" = 11.8
  dimension "d1277" = 45.9145
  dimension "d1278" = 2.4
  dimension "d1279" = 5
  constraint horizontal L0
  constraint vertical L1
  constraint horizontal L2
  constraint vertical L3
  measures "d1276" horizontal distance of origin L0.start
  measures "d1277" vertical distance of origin L0.start
  measures "d1278" distance of L0.start L0.end
  measures "d1279" distance of L0.end L1.end
extrude "SW4 support 1 reinforced stem" add sketch "SW4 support 1 reinforced stem profile" along normal blind 13.9777 bodies 3
sketch "SW4 support 1 profile" plane through (0, 0, 2) normal (0, 0, 1) x (1, 0, 0)
  line L0 (12.5, 46.9145) -> (13.5, 46.9145)
  line L1 (13.5, 46.9145) -> (13.5, 49.9145)
  line L2 (13.5, 49.9145) -> (12.5, 49.9145)
  line L3 (12.5, 49.9145) -> (12.5, 46.9145)
  dimension "d1282" = 12.5
  dimension "d1283" = 46.9145
  dimension "d1284" = 1
  dimension "d1285" = 3
  constraint horizontal L0
  constraint vertical L1
  constraint horizontal L2
  constraint vertical L3
  measures "d1282" horizontal distance of origin L0.start
  measures "d1283" vertical distance of origin L0.start
  measures "d1284" distance of L0.start L0.end
  measures "d1285" distance of L0.end L1.end
extrude "SW4 support 1" add sketch "SW4 support 1 profile" along normal blind 16.4777 bodies 3
sketch "SW4 support 1 cap profile" plane through (0, -1.1931, 13.6376) normal (0, -0.087156, 0.996195) x (1, 0, 0)
  line L0 (12.4, 47.7972) -> (13.6, 47.7972)
  line L1 (13.6, 47.7972) -> (13.6, 51.7972)
  line L2 (13.6, 51.7972) -> (12.4, 51.7972)
  line L3 (12.4, 51.7972) -> (12.4, 47.7972)
  dimension "d1288" = 12.4
  dimension "d1289" = 47.7972
  dimension "d1290" = 1.2
  dimension "d1291" = 4
  constraint horizontal L0
  constraint vertical L1
  constraint horizontal L2
  constraint vertical L3
  measures "d1288" horizontal distance of origin L0.start
  measures "d1289" vertical distance of origin L0.start
  measures "d1290" distance of L0.start L0.end
  measures "d1291" distance of L0.end L1.end
extrude "SW4 support 1 inclined cap" cut sketch "SW4 support 1 cap profile" along normal blind 39.0612 bodies 3
sketch "SW4 support 2 reinforced stem profile" plane through (0, 0, 2) normal (0, 0, 1) x (1, 0, 0)
  line L0 (16.8, 45.9145) -> (19.2, 45.9145)
  line L1 (19.2, 45.9145) -> (19.2, 50.9145)
  line L2 (19.2, 50.9145) -> (16.8, 50.9145)
  line L3 (16.8, 50.9145) -> (16.8, 45.9145)
  dimension "d1294" = 16.8
  dimension "d1295" = 45.9145
  dimension "d1296" = 2.4
  dimension "d1297" = 5
  constraint horizontal L0
  constraint vertical L1
  constraint horizontal L2
  constraint vertical L3
  measures "d1294" horizontal distance of origin L0.start
  measures "d1295" vertical distance of origin L0.start
  measures "d1296" distance of L0.start L0.end
  measures "d1297" distance of L0.end L1.end
extrude "SW4 support 2 reinforced stem" add sketch "SW4 support 2 reinforced stem profile" along normal blind 13.9777 bodies 3
sketch "SW4 support 2 profile" plane through (0, 0, 2) normal (0, 0, 1) x (1, 0, 0)
  line L0 (17.5, 46.9145) -> (18.5, 46.9145)
  line L1 (18.5, 46.9145) -> (18.5, 49.9145)
  line L2 (18.5, 49.9145) -> (17.5, 49.9145)
  line L3 (17.5, 49.9145) -> (17.5, 46.9145)
  dimension "d1300" = 17.5
  dimension "d1301" = 46.9145
  dimension "d1302" = 1
  dimension "d1303" = 3
  constraint horizontal L0
  constraint vertical L1
  constraint horizontal L2
  constraint vertical L3
  measures "d1300" horizontal distance of origin L0.start
  measures "d1301" vertical distance of origin L0.start
  measures "d1302" distance of L0.start L0.end
  measures "d1303" distance of L0.end L1.end
extrude "SW4 support 2" add sketch "SW4 support 2 profile" along normal blind 16.4777 bodies 3
sketch "SW4 support 2 cap profile" plane through (0, -1.1931, 13.6376) normal (0, -0.087156, 0.996195) x (1, 0, 0)
  line L0 (17.4, 47.7972) -> (18.6, 47.7972)
  line L1 (18.6, 47.7972) -> (18.6, 51.7972)
  line L2 (18.6, 51.7972) -> (17.4, 51.7972)
  line L3 (17.4, 51.7972) -> (17.4, 47.7972)
  dimension "d1306" = 17.4
  dimension "d1307" = 47.7972
  dimension "d1308" = 1.2
  dimension "d1309" = 4
  constraint horizontal L0
  constraint vertical L1
  constraint horizontal L2
  constraint vertical L3
  measures "d1306" horizontal distance of origin L0.start
  measures "d1307" vertical distance of origin L0.start
  measures "d1308" distance of L0.start L0.end
  measures "d1309" distance of L0.end L1.end
extrude "SW4 support 2 inclined cap" cut sketch "SW4 support 2 cap profile" along normal blind 39.0612 bodies 3
sketch "SW5 receiver profile" plane through (0, -2.1431, 24.4961) normal (0, -0.087156, 0.996195) x (1, 0, 0)
  line L0 (30.8, 42.1972) -> (49.2, 42.1972)
  line L1 (49.2, 42.1972) -> (49.2, 59.7972)
  line L2 (49.2, 59.7972) -> (30.8, 59.7972)
  line L3 (30.8, 59.7972) -> (30.8, 42.1972)
  dimension "d1312" = 30.8
  dimension "d1313" = 42.1972
  dimension "d1314" = 18.4
  dimension "d1315" = 17.6
  constraint horizontal L0
  constraint vertical L1
  constraint horizontal L2
  constraint vertical L3
  measures "d1312" horizontal distance of origin L0.start
  measures "d1313" vertical distance of origin L0.start
  measures "d1314" distance of L0.start L0.end
  measures "d1315" distance of L0.end L1.end
extrude "SW5 integrated receiver" add sketch "SW5 receiver profile" against normal blind 11.5 bodies 2
sketch "SW5 switch lower clearance profile" plane through (0, -2.1431, 24.4961) normal (0, -0.087156, 0.996195) x (1, 0, 0)
  line L0 (32, 42.9972) -> (48, 42.9972)
  line L1 (48, 42.9972) -> (48, 58.9972)
  line L2 (48, 58.9972) -> (32, 58.9972)
  line L3 (32, 58.9972) -> (32, 42.9972)
  dimension "d1318" = 32
  dimension "d1319" = 42.9972
  dimension "d1320" = 16
  dimension "d1321" = 16
  constraint horizontal L0
  constraint vertical L1
  constraint horizontal L2
  constraint vertical L3
  measures "d1318" horizontal distance of origin L0.start
  measures "d1319" vertical distance of origin L0.start
  measures "d1320" distance of L0.start L0.end
  measures "d1321" distance of L0.end L1.end
extrude "SW5 switch lower clearance" cut sketch "SW5 switch lower clearance profile" against normal blind 5.5 bodies 2
sketch "SW5 holder pocket profile" plane through (0, -1.6638, 19.017) normal (0, -0.087156, 0.996195) x (1, 0, 0)
  line L0 (34.2843, 45.9226) -> (45.7157, 45.9226)
  line L1 (45.7157, 45.9226) -> (45.7157, 56.0717)
  line L2 (45.7157, 56.0717) -> (34.2843, 56.0717)
  line L3 (34.2843, 56.0717) -> (34.2843, 45.9226)
  dimension "d1324" = 34.2843
  dimension "d1325" = 45.9226
  dimension "d1326" = 11.4315
  dimension "d1327" = 10.1491
  constraint horizontal L0
  constraint vertical L1
  constraint horizontal L2
  constraint vertical L3
  measures "d1324" horizontal distance of origin L0.start
  measures "d1325" vertical distance of origin L0.start
  measures "d1326" distance of L0.start L0.end
  measures "d1327" distance of L0.end L1.end
extrude "SW5 open-bottom holder pocket" cut sketch "SW5 holder pocket profile" against normal blind 6.2 bodies 2
sketch "SW5 spring 1 release 1 profile" plane through (0, -2.056, 23.4999) normal (0, -0.087156, 0.996195) x (1, 0, 0)
  line L0 (30.7, 53.0972) -> (34.2843, 53.0972)
  line L1 (34.2843, 53.0972) -> (34.2843, 53.6972)
  line L2 (34.2843, 53.6972) -> (30.7, 53.6972)
  line L3 (30.7, 53.6972) -> (30.7, 53.0972)
  dimension "d1330" = 30.7
  dimension "d1331" = 53.0972
  dimension "d1332" = 3.5843
  dimension "d1333" = 0.6
  constraint horizontal L0
  constraint vertical L1
  constraint horizontal L2
  constraint vertical L3
  measures "d1330" horizontal distance of origin L0.start
  measures "d1331" vertical distance of origin L0.start
  measures "d1332" distance of L0.start L0.end
  measures "d1333" distance of L0.end L1.end
extrude "SW5 spring 1 release 1" cut sketch "SW5 spring 1 release 1 profile" against normal blind 10.7 bodies 2
sketch "SW5 spring 1 release 2 profile" plane through (0, -2.056, 23.4999) normal (0, -0.087156, 0.996195) x (1, 0, 0)
  line L0 (30.7, 55.6972) -> (34.2843, 55.6972)
  line L1 (34.2843, 55.6972) -> (34.2843, 56.2972)
  line L2 (34.2843, 56.2972) -> (30.7, 56.2972)
  line L3 (30.7, 56.2972) -> (30.7, 55.6972)
  dimension "d1336" = 30.7
  dimension "d1337" = 55.6972
  dimension "d1338" = 3.5843
  dimension "d1339" = 0.6
  constraint horizontal L0
  constraint vertical L1
  constraint horizontal L2
  constraint vertical L3
  measures "d1336" horizontal distance of origin L0.start
  measures "d1337" vertical distance of origin L0.start
  measures "d1338" distance of L0.start L0.end
  measures "d1339" distance of L0.end L1.end
extrude "SW5 spring 1 release 2" cut sketch "SW5 spring 1 release 2 profile" against normal blind 10.7 bodies 2
sketch "SW5 spring 1 inner clearance profile" plane through (0, -1.6638, 19.017) normal (0, -0.087156, 0.996195) x (1, 0, 0)
  line L0 (31.6, 53.6972) -> (34.2843, 53.6972)
  line L1 (34.2843, 53.6972) -> (34.2843, 55.6972)
  line L2 (34.2843, 55.6972) -> (31.6, 55.6972)
  line L3 (31.6, 55.6972) -> (31.6, 53.6972)
  dimension "d1342" = 31.6
  dimension "d1343" = 53.6972
  dimension "d1344" = 2.6843
  dimension "d1345" = 2
  constraint horizontal L0
  constraint vertical L1
  constraint horizontal L2
  constraint vertical L3
  measures "d1342" horizontal distance of origin L0.start
  measures "d1343" vertical distance of origin L0.start
  measures "d1344" distance of L0.start L0.end
  measures "d1345" distance of L0.end L1.end
extrude "SW5 spring 1 inner clearance" cut sketch "SW5 spring 1 inner clearance profile" against normal blind 6.2 bodies 2
sketch "SW5 spring 1 hook profile" plane through (0, -1.2106, 13.8368) normal (0, -0.087156, 0.996195) x (1, 0, 0)
  line L0 (30.8, 53.6972) -> (34.7843, 53.6972)
  line L1 (34.7843, 53.6972) -> (34.7843, 55.6972)
  line L2 (34.7843, 55.6972) -> (30.8, 55.6972)
  line L3 (30.8, 55.6972) -> (30.8, 53.6972)
  dimension "d1348" = 30.8
  dimension "d1349" = 53.6972
  dimension "d1350" = 3.9843
  dimension "d1351" = 2
  constraint horizontal L0
  constraint vertical L1
  constraint horizontal L2
  constraint vertical L3
  measures "d1348" horizontal distance of origin L0.start
  measures "d1349" vertical distance of origin L0.start
  measures "d1350" distance of L0.start L0.end
  measures "d1351" distance of L0.end L1.end
extrude "SW5 spring 1 retaining hook" add sketch "SW5 spring 1 hook profile" against normal blind 0.8 bodies 2
chamfer "SW5 spring 1 45 degree lead-in" distance 0.35 angle 45 1 edges at (34.7843, 53.3482, 17.807) tangent chain off on bodies 2